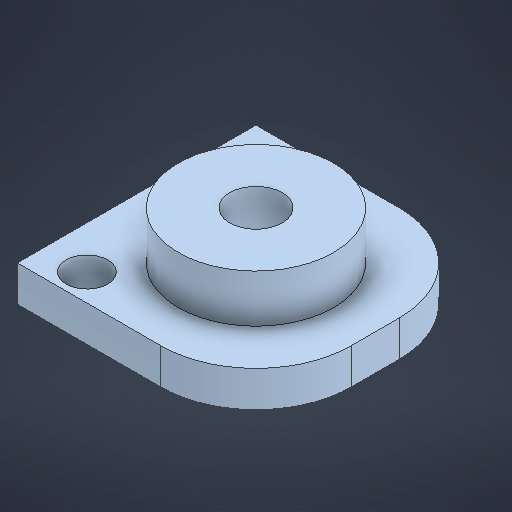
# Autodesk Inventor part: 01_5_2_supports_moteurs_adaptateur_axe_petit_robot_v1
Saved by Autodesk Inventor 2026 (Build 300175000, 175)
## iProperties
Created: 2025-05-22
Part Number: 01_5_2_supports_moteurs_adaptateur_axe_petit_robot_v1
Material: Générique
Document SubType Name: Modeling
Designer: virgi
Density: 1 g/cm^3
Appearance: Par défaut
Author: virgi
Autodesk Inventor part; units mm, degrees
ref_plane "YZ Plane" through (0, 0, 0) normal (1, 0, 0) x (0, 1, 0)
ref_plane "XZ Plane" through (0, 0, 0) normal (0, 1, 0) x (-1, 0, 0)
ref_plane "XY Plane" through (0, 0, 0) normal (0, 0, 1) x (1, 0, 0)
sketch "Esquisse1" plane through (0, 0, 0) normal (0, 1, 0) x (-1, 0, 0)
  line L0 (0, 0) -> (20, 0)
  line L1 (20, 0) -> (20, -20)
  line L2 (20, -20) -> (0, -20)
  line L3 (0, -20) -> (0, 0)
  dimension "d3" = 20
  dimension "d4" = 20
  constraints: 8 end point, 2 parallel, 1 horizontal, 1 perpendicular
  measures "d3" distance of L0.end L1.end
  measures "d4" distance of L1.end L2.end
extrude "Extrusion1" add sketch "Esquisse1" along normal blind 3
sketch "Esquisse2" plane through (0, 3, 0) normal (0, 1, 0) x (1, 0, 0)
  circle A0 centre (-10, 10) radius 6.5
  line L0 (0, 20) -> (-20, 20) projected
  line L1 (-25.5279, 10) -> (5.0346, 10) construction
  line L2 (0, 0) -> (0, 20) construction
  line L3 (-20, 20) -> (-20, 0) projected
  dimension "d7" = 13
  dimension "d9" = 10
  dimension "d23" = 10
  constraints: 2 end point, 1 centre point, 1 horizontal, 1 point on line
  measures "d7" diameter of A0
  measures "d9" distance between parallel lines of L1 L0
  measures "d23" distance from line of L3 A0.centre
extrude "Extrusion2" add sketch "Esquisse2" along normal blind 4
sketch "Esquisse3" plane through (0, 3, 0) normal (0, 1, 0) x (1, 0, 0)
  circle A0 centre (-10, 10) radius 6.5 projected
  line L0 (-20, 0) -> (0, 0) projected
  point P0 (-16.423, 2.25)
  point P1 (-16.423, 17.75)
  dimension "d20" = 15.5
  dimension "d21" = 0
  dimension "d22" = 6.423
  dimension "d24" = 2.25
  measures "d20" distance of point (-16.423, 17.75) point (-16.423, 2.25)
  measures "d21" horizontal distance of point (-16.423, 17.75) point (-16.423, 2.25)
  measures "d22" horizontal distance of A0.centre point (-16.423, 2.25)
  measures "d24" distance from line of L0 point (-16.423, 2.25)
hole "Perçage1" at (-16.423, 3, -2.25) at (-16.423, 3, -17.75) direction (0, -1, 0) diameter 3.5 end through all
fillet "Congé1" radius 8 2 edges at (0, 1.5, 0) (0, 1.5, -20)
sketch "Esquisse5" plane through (-10, 7, -10) normal (0, 1, 0) x (1, 0, 0)
  circle A0 centre (0, 0) radius 2.2
  circle A1 centre (0, 0) radius 6.5 projected
  point P0 (10, -10)
  dimension "d33" = 4.4
  constraints: 1 centre point, 1 concentric
  measures "d33" diameter of A0
extrude "Extrusion3" cut sketch "Esquisse5" against normal blind 10 contours A0
